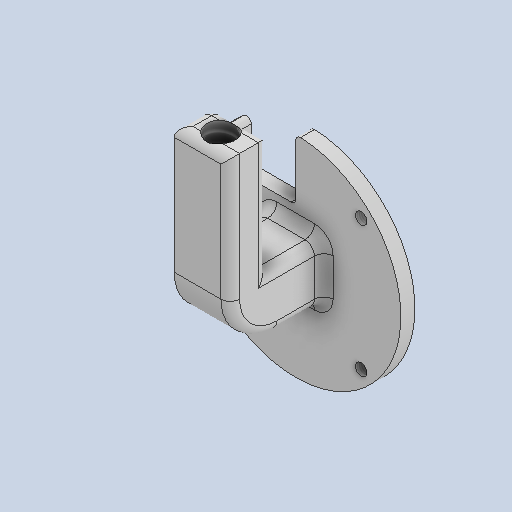
# Autodesk Inventor part: 零件3
Saved by Autodesk Inventor 2025 (Build 290162000, 162)
## iProperties
Created: 2026-11-03
Part Number: 零件3
Material: 常规
Document SubType Name: Modeling
Designer: test
Density: 1 g/cm^3
Appearance: 默认
Author: test
Autodesk Inventor part; units mm, degrees
ref_plane "YZ Plane" through (0, 0, 0) normal (1, 0, 0) x (0, 1, 0)
ref_plane "XZ Plane" through (0, 0, 0) normal (0, 1, 0) x (-1, 0, 0)
ref_plane "XY Plane" through (0, 0, 0) normal (0, 0, 1) x (1, 0, 0)
sketch "草图1" plane through (0, 0, 0) normal (0, 0, 1) x (1, 0, 0)
  line L0 (-14, 14) -> (14, 14)
  line L1 (14, 14) -> (14, -14)
  line L2 (14, -14) -> (-14, -14)
  line L3 (-14, -14) -> (-14, 14)
  line L4 (-14, 14) -> (14, -14) construction
  line L5 (14, 14) -> (-14, -14) construction
  circle A0 centre (0, 0) radius 22.5
  circle A1 centre (-14, 14) radius 1.25
  circle A2 centre (-14, -14) radius 1.25
  circle A3 centre (14, -14) radius 1.25
  circle A4 centre (14, 14) radius 1.25
  dimension "d0" = 28
  dimension "d1" = 45
  dimension "d2" = 2.5
  dimension "d3" = 2.5
  dimension "d4" = 2.5
  dimension "d5" = 2.5
  constraints: 12 end point, 5 centre point, 5 coincident, 2 midpoint, 2 parallel, 2 perpendicular, 1 horizontal
  measures "d0" distance of L0.start L0.end
  measures "d1" diameter of A0
  measures "d2" diameter of A1
  measures "d3" diameter of A2
  measures "d4" diameter of A3
  measures "d5" diameter of A4
extrude "拉伸1" add sketch "草图1" along normal blind 3 contours L0 A4 L1 A3 L2 A2 L3 A1 | A0
thread "螺纹2" size "M2.5x0.45" designation "M2.5" class "6H" standard "GB Metric profile" length 15.103
thread "螺纹3" size "M2.5x0.45" designation "M2.5" class "6H" standard "GB Metric profile" length 15.103
thread "螺纹4" size "M2.5x0.45" designation "M2.5" class "6H" standard "GB Metric profile" length 15.103
thread "螺纹5" size "M2.5x0.45" designation "M2.5" class "6H" standard "GB Metric profile" length 15.103
sketch "草图4" plane through (0, 0, 3) normal (0, 0, 1) x (1, 0, 0)
  circle A0 centre (0, 0) radius 9.5 projected
  line L0 (0, 9.5) -> (-12.5, 9.5)
  line L1 (-12.5, 9.5) -> (-12.5, 23.5)
  line L2 (-12.5, 23.5) -> (0, 23.5)
  line L3 (0, 23.5) -> (0, 9.5)
  circle A1 centre (0, 0) radius 9.5
  dimension "d25" = 12.5
  dimension "d26" = 14
  constraints: 8 end point, 2 parallel, 2 vertical alignment, 1 coincident, 1 horizontal, 1 perpendicular, 3 other
  measures "d25" distance of L1.end L2.end
  measures "d26" distance of L0.end L1.end
extrude "拉伸4" cut sketch "草图4" against normal blind 10 contours L0 L1 L2 L3
fillet "圆角2" radius 1 4 edges at (0, 9.5, 1.5) (0, 22.5, 1.5) (-12.5, 9.5, 1.5) (-12.5, 18.7083, 1.5)
sketch "草图6" plane through (0, 0, 3) normal (0, 0, 1) x (1, 0, 0)
  line L0 (-6, -6) -> (6, -6)
  line L1 (6, -6) -> (6, 6)
  line L2 (6, 6) -> (-6, 6)
  line L3 (-6, 6) -> (-6, -6)
  line L4 (-6, -6) -> (6, 6) construction
  line L5 (6, -6) -> (-6, 6) construction
  point P0 (0, 0)
  dimension "d30" = 12
  constraints: 12 end point, 2 midpoint, 2 parallel, 2 perpendicular, 1 horizontal
  measures "d30" distance of L2.end L0.start
extrude "拉伸5" add sketch "草图6" along normal blind 20
sketch "草图7" plane through (-6, 6, 3) normal (0, 1, 0) x (1, 0, 0)
  line L0 (12, -20) -> (0, -20) projected
  line L1 (12, 0) -> (12, -20) projected
  line L2 (0, -20) -> (12, -20)
  line L3 (12, -20) -> (12, -12)
  line L4 (12, -12) -> (0, -12)
  line L5 (0, -12) -> (0, -20)
  point P0 (6, 3)
  dimension "d33" = 8
  constraints: 8 end point, 2 parallel, 1 horizontal, 1 perpendicular, 1 point on line
  measures "d33" distance of L4.end L0.end
extrude "拉伸6" add sketch "草图7" along normal blind 25
sketch "草图8" plane through (-6, 31, 3) normal (0, 1, 0) x (1, 0, 0)
  line L0 (0, 0) -> (0, -12) projected
  line L1 (12, -20) -> (0, -12)
  line L2 (0, -12) -> (0, -20)
  line L3 (12, 0) -> (12, -12) projected
  line L4 (0, -20) -> (12, -12)
  circle A0 centre (6, -16) radius 3.075
  point P0 (6, 3)
  dimension "d36" = 6.15
  constraints: 6 end point, 1 centre point, 1 collinear, 1 midpoint
  measures "d36" diameter of A0
extrude "拉伸7" cut sketch "草图8" against normal blind 25 contours A0 L4 L1 | L1 L4 A0 | L4 A0 L1 | L1 A0 L4
thread "螺纹6" size "Rc 6" standard "DIN Pipe Taper Internal" length 43.6
fillet "圆角3" radius 10 1 edges at (0, -6, 23)
fillet "圆角4" radius 2 14 edges at (6, -3.0711, 20.0711) (6, -6, 8) (6, 17.5, 23) (6, 6, 9) (6, 18.5, 15) (-6, 6, 9) (-6, 18.5, 15) (0, 31, 23) (-6, 31, 19) (0, 31, 15) (6, 0, 3) (0, 6, 3) (-6, 0, 3) (0, -6, 3)
